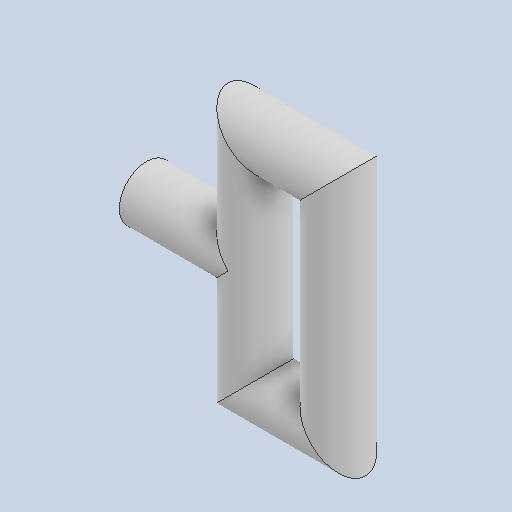
# Autodesk Inventor part: wire1
Saved by Autodesk Inventor 2026.1 (Build 301233020, 233B)
## iProperties
Created: 2025-11-30
Part Number: wire1
Material: Generico
Document SubType Name: Modeling
Designer: maxbu
Density: 1 g/cm^3
Appearance: Default
Author: maxbu
Autodesk Inventor part; units mm, degrees
ref_plane "YZ Plane" through (0, 0, 0) normal (1, 0, 0) x (0, 1, 0)
ref_plane "XZ Plane" through (0, 0, 0) normal (0, 1, 0) x (-1, 0, 0)
ref_plane "XY Plane" through (0, 0, 0) normal (0, 0, 1) x (1, 0, 0)
sketch "Schizzo1" plane through (0, 0, 0) normal (0, 0, 1) x (1, 0, 0)
  line L0 (0, 0) -> (0, 3)
  line L1 (0, 3) -> (2.3, 3)
  line L2 (2.3, 3) -> (2.3, 0)
  line L3 (2.3, 0) -> (7.3, 0)
  line L4 (0, 0) -> (0, -3)
  line L5 (0, -3) -> (2.3, -3)
  line L6 (2.3, -3) -> (2.3, 0)
  line L7 (2.3, 0) -> (0, 0) construction
  dimension "d0" = 3
  dimension "d1" = 2.3
  dimension "d5" = 5
  constraints: 16 end point, 5 perpendicular, 2 vertical, 1 collinear, 1 horizontal
  measures "d0" distance of L0.start L0.end
  measures "d1" distance of L0.end L1.end
  measures "d5" distance of L2.end L3.end
sketch "Schizzo2" plane through (0, 0, 0) normal (0, 1, 0) x (-1, 0, 0)
  circle A0 centre (0, 0) radius 0.75
  dimension "d2" = 1.5
  constraints: 1 centre point, 1 coincident
  measures "d2" diameter of A0
sweep "Sweep1" add profiles "Schizzo2" path "Schizzo1" path curves L0 L1 L2 L6 L5 L4
sketch "Schizzo3" plane through (0, 0, 0) normal (1, 0, 0) x (0, 1, 0)
  circle A0 centre (0, 0) radius 0.75
  dimension "d6" = 1.5
  constraints: 1 centre point, 1 coincident
  measures "d6" diameter of A0
extrude "Estrusione1" add sketch "Schizzo3" against normal blind 3
